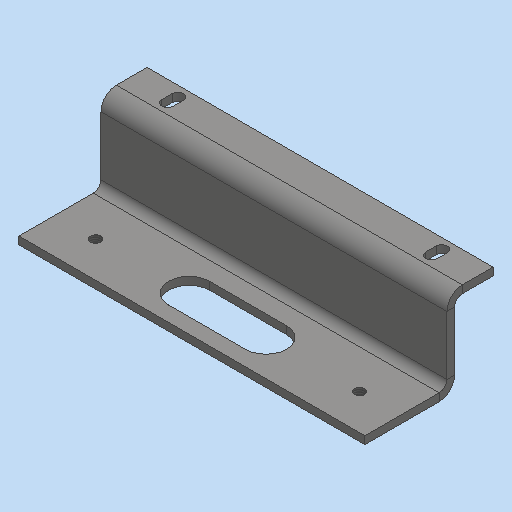
# Autodesk Inventor part: MM0948AN140_G01_105
Saved by Autodesk Inventor 2023.3 (Build 273359000, 359)
## iProperties
Created: 2023-03-23
Part Number: MM0948AN140_G01_105
Material: 1.4301 X5CrNi18-10
Description: =<RBPARTNOTITLE2>
Document SubType Name: Blech
Designer: FH/Wi
Mass: 230.149 g
Surface Area: 213.66 cm^2
Volume: 29.3184 cm^3
Density: 7.85 g/cm^3
Appearance: Stahl - rostfrei AnP
Sheet Metal Rule: Standard
Flat Pattern Width: 7.75717 cm
Flat Pattern Length: 13.5 cm
Flat Pattern Area: 104.722 cm^2
Sheet Metal Width: 77,572 mm
Sheet Metal Length: 135,000 mm
Sheet Metal Area: 10472,177 mm^2
AnP_Kategorie: 1
AnP_Material: =<Material>
MaxAbmaße: 3 x 77,572 x 135 (FM)
AnP_TemplVers: 20200821
RBDOCUMENTTYPE: DRF
RBDOCUMENTVERSION: 00
RBDRAWINGMAINSCALE: 1:1
RBDRAWINGMISSINGSPEC: --
RBDRAWINGVOLUME: --
RBDSV1: 0850
RBGBEDGESIN1: +0,5
RBGBEDGESIN2: +0,2
RBGBEDGESOUT1: -0,3
RBGBEDGESOUT2: -0,1
RBMATERIAL: =<Material>
RBMATMEETS: --
RBMATNO: =<Part Number>
RBPARTMADEOF: 3 x 77,572 x 135 (FM)
RBPARTNO: SIEHE MNR
RBPARTNOTITLE1: manufactured part
RBPARTNOTITLE2: Anfertigungsteil
RBPARTSAFETYINDICATOR: --
RBSURFACE: --
RBSURFACE2: --
RBZEDGESNORM: ISO13715:2002-06
RBZGENDIMCLASS: m
RBZGENDIMNORM: ISO 2768-1:1989-11
RBZGENGEOCLASS: H
RBZGENGEONORM: ISO 2768-2:1989-11
RBZSURFACENORM: ISO13D2:2002-02
RBZTOLERANCENORM: ISO 14405-1:2010-12
AnP_Kommentar_aktuell: =<Comments>
AnP_Material_aktuell: =<Material>
Author: FH/Wi
Keywords: =<RBPARTMADEOF>
Comments: =<RBSURFACE2>
Revision Number: 01
Autodesk Inventor part; units mm, degrees
ref_plane "YZ Plane" through (0, 0, 0) normal (1, 0, 0) x (0, 1, 0)
ref_plane "XZ Plane" through (0, 0, 0) normal (0, 1, 0) x (-1, 0, 0)
ref_plane "XY Plane" through (0, 0, 0) normal (0, 0, 1) x (1, 0, 0)
sketch "Skizze2" plane through (0, 0, 0) normal (0, 0, 1) x (1, 0, 0)
  line L0 (-67.5, 35) -> (67.5, 35)
  line L1 (67.5, 35) -> (67.5, 0)
  line L2 (67.5, 0) -> (-67.5, 0)
  line L3 (-67.5, 0) -> (-67.5, 35)
  point P0 (0, 0)
  point P1 (0, 0)
  dimension "d8" = 135
  dimension "d9" = 35
  measures "d8" distance of L1.end L2.end
  measures "d9" distance of L2.end L0.start
extrude "Grobblech1" add sketch "Skizze2" along normal blind 3
sketch "Skizze3" plane through (-67.5, 32, 0) normal (0, 1, 0) x (-1, 0, 0)
  line L0 (-135, 0) -> (0, 0)
  line L1 (0, 0) -> (0, 35)
  line L2 (0, 35) -> (-135, 35)
  line L3 (-135, 35) -> (-135, 0)
  constraints: 6 end point, 1 horizontal, 1 perpendicular, 1 vertical
edge flange "Lasche1" height 35 angle 90 thickness 3 bend radius 3 thickness toward (0, 1, 0) relief straight relief width 3 relief depth 1.5 edges at (0, 35, 3) wall of the first edge with corners at (67.5, 32, 0) (-67.5, 32, 0) (-67.5, 32, 35) (67.5, 32, 35)
bend "Biegung1"
corner "Ecke1"
sketch "Skizze4" plane through (67.5, 32, 32) normal (0, 0, 1) x (1, 0, 0)
  line L0 (-135, 0) -> (0, 0)
  line L1 (0, 0) -> (0, 18)
  line L2 (0, 18) -> (-135, 18)
  line L3 (-135, 18) -> (-135, 0)
  constraints: 6 end point, 1 horizontal, 1 perpendicular, 1 vertical
edge flange "Lasche2" height 18 angle 90 thickness 3 bend radius 3 thickness toward (0, 0, 1) relief straight relief width 3 relief depth 1.5 edges at (0, 35, 35) wall of the first edge with corners at (-67.5, 32, 32) (67.5, 32, 32) (67.5, 50, 32) (-67.5, 50, 32)
bend "Biegung2"
corner "Ecke2"
sketch "Skizze5" plane through (0, 0, 3) normal (0, 0, 1) x (1, 0, 0)
  line L0 (67.5, 0) -> (-67.5, 0) projected
  line L1 (0, 0) -> (0, 14.836)
  point P0 (-51.5, 13.9)
  point P1 (51.5, 13.9)
  dimension "d31" = 13.9
  dimension "d32" = 103
  constraints: 2 end point, 1 symmetric about line, 1 vertical
  measures "d31" distance from line of L0 point (-51.5, 13.9)
  measures "d32" distance of point (51.5, 13.9) point (-51.5, 13.9)
hole "Bohrung1" at (-51.5, 13.9, 3) at (51.5, 13.9, 3) direction (0, 0, -1) diameter 4.134 end through all thread size "M5x0.8" designation "M5" class "6H" standard "ISO Metric profile"
sketch "Skizze6" plane through (0, 0, 0) normal (0, 0, -1) x (-1, 0, 0)
  line L0 (-15, 13.9) -> (15, 13.9) construction
  line L1 (-15, 5.9) -> (15, 5.9)
  line L2 (15, 21.9) -> (-15, 21.9)
  arc A0 (-15, 21.9) -> (-15, 5.9) centre (-15, 13.9) ccw
  arc A1 (15, 5.9) -> (15, 21.9) centre (15, 13.9) ccw
  line L3 (-51.5, 13.9) -> (0, 13.9) construction
  line L4 (0, 13.9) -> (0, 0) construction
  circle A2 centre (-51.5, 13.9) radius 2.067 construction
  dimension "d26" = 90
  dimension "d40" = 16
  dimension "d41" = 30
  constraints: 12 end point, 4 point on circle, 4 tangent, 2 centre point, 2 horizontal, 1 coincident, 1 midpoint, 1 parallel, 1 vertical
  measures "d40" distance between parallel lines of L1 L2
  measures "d41" distance of L2.start L2.end
extrude "Ausklinkung1" cut sketch "Skizze6" against normal blind 3
sketch "Skizze7" plane through (67.5, 50, 32) normal (0, 0, -1) x (-1, 0, 0)
  line L0 (16, -4) -> (16, -8) construction
  line L1 (13.75, -4) -> (13.75, -8)
  line L2 (18.25, -8) -> (18.25, -4)
  arc A0 (18.25, -4) -> (13.75, -4) centre (16, -4) ccw
  arc A1 (13.75, -8) -> (18.25, -8) centre (16, -8) ccw
  line L3 (119, -4) -> (119, -8) construction
  line L4 (116.75, -4) -> (116.75, -8)
  line L5 (121.25, -8) -> (121.25, -4)
  arc A2 (121.25, -4) -> (116.75, -4) centre (119, -4) ccw
  arc A3 (116.75, -8) -> (121.25, -8) centre (119, -8) ccw
  circle A4 centre (16, -36.1) radius 2.067 projected
  circle A5 centre (119, -36.1) radius 2.067 projected
  line L6 (135, 0) -> (0, 0) projected
  line L7 (0, -12) -> (135, -12) projected
  point P0 (67.5, -50)
  point P1 (16, -6)
  point P2 (119, -6)
  dimension "d44" = 4.5
  dimension "d46" = 4
  dimension "d49" = 6
  dimension "d50" = 4
  dimension "d51" = 4
  constraints: 16 end point, 8 point on circle, 8 tangent, 4 centre point, 4 parallel, 2 midpoint, 2 vertical alignment, 1 equal radius, 1 horizontal alignment, 1 vertical
  measures "d44" distance between parallel lines of L2 L1
  measures "d46" distance of L2.start L2.end
  measures "d49" distance from line of point (16, -6) L6
  measures "d50" distance from line of L0.start L6
  measures "d51" distance from line of L7 L0.end
extrude "Ausklinkung2" cut sketch "Skizze7" against normal blind 3 contours A0 L2 A1 L1 | A2 L5 A3 L4
equation "\"d42\" = Stärke"
equation "\"d47\" = Stärke"
equation "\"d10\" = Stärke"
equation "\"d11\" = BreiteBiegungsfreistellung"
equation "\"d12\" = TiefeBiegungsfreistellung"
equation "\"d13\" = MinimalRest"
equation "\"d14\" = Übergangsradius"
equation "\"d17\" = Biegeradius"
equation "\"d18\" = GrößeEckenfreistellung"
equation "\"d19\" = Abstandsgröße"
equation "\"d20\" = JacobiRadiusGröße"
equation "\"d21\" = BreiteBiegungsfreistellung"
equation "\"d22\" = TiefeBiegungsfreistellung"
equation "\"d23\" = MinimalRest"
equation "\"d24\" = Übergangsradius"
equation "\"d27\" = Biegeradius"
equation "\"d28\" = GrößeEckenfreistellung"
equation "\"d29\" = Abstandsgröße"
equation "\"d30\" = JacobiRadiusGröße"
equation "\"Biegeradius\" = Stärke"
equation "\"BreiteBiegungsfreistellung\" = Stärke"
equation "\"TiefeBiegungsfreistellung\" = 0.5 * Stärke"
equation "\"GrößeEckenfreistellung\" = 4 * Stärke"
equation "\"MinimalRest\" = 2 * Stärke"
equation "\"Übergangsradius\" = Biegeradius"
equation "\"JacobiRadiusGröße\" = Stärke"
equation "\"Abstandsgröße\" = Stärke"
equation "\"Stärke\" = 3"
